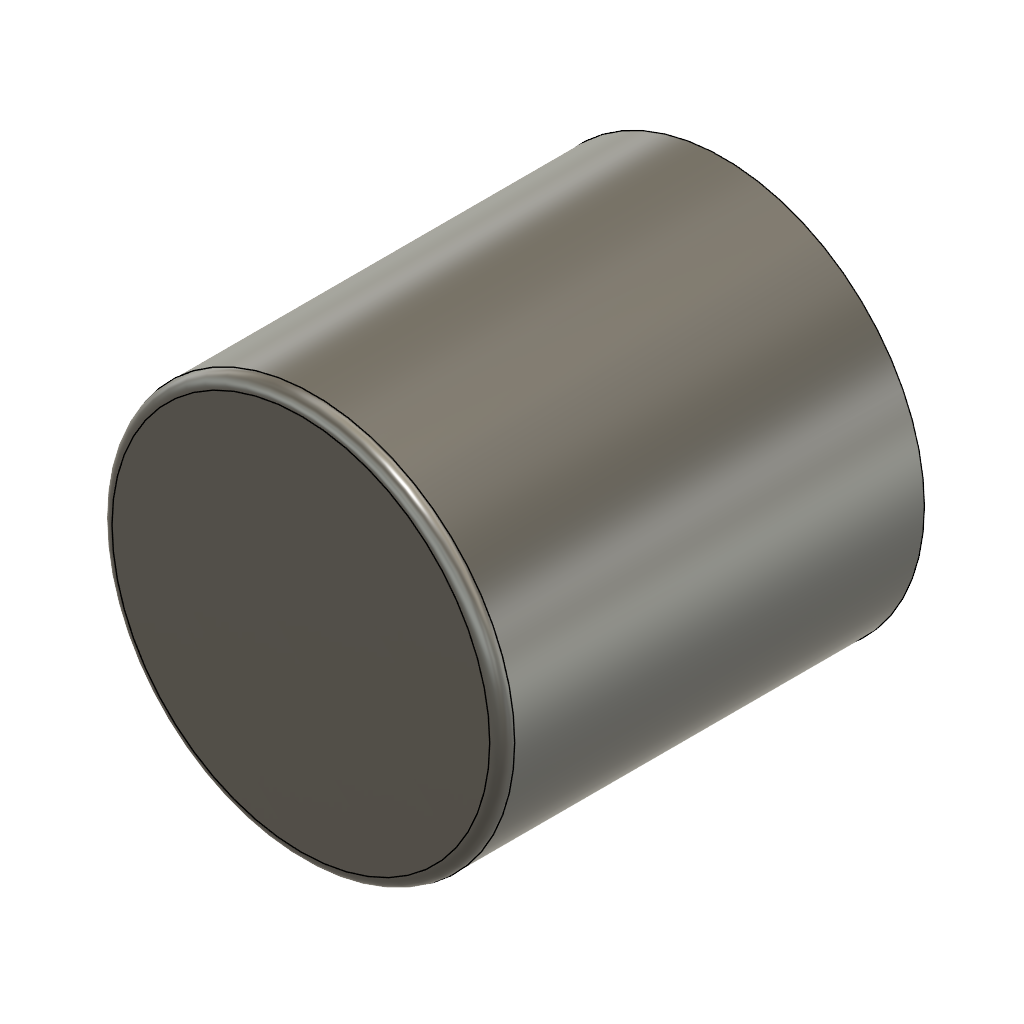
owner (Autodesk Fusion 360 design; units mm, degrees)
part number: 2026-11-25-22-35-58-951
Autodesk Fusion 360 part; units mm, degrees
sketch "Disc sketch" plane through (0, 0, 0) normal (0, 0, 1) x (1, 0, 0)
  circle A0 centre (0, 0) radius 11.3
extrude "Disc extrude" add sketch "Disc sketch" along normal blind 23.7
fillet "Rim round" radius 0.7 1 edges at (-10.5353, -4.0863, 23.7)
